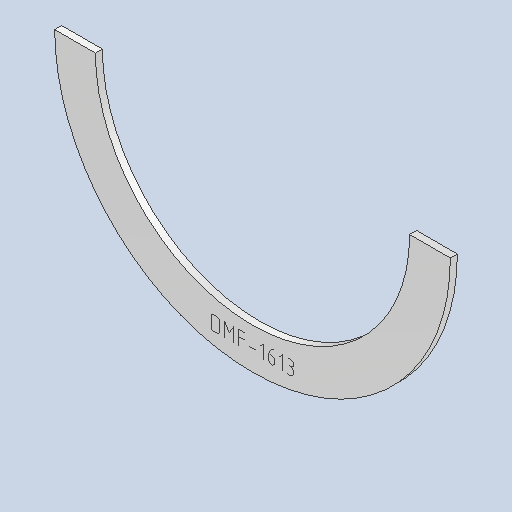
# Autodesk Inventor part: DMF-1613 Front Connector Ring 3 Half
Saved by Autodesk Inventor 2026.2 (Build 302298000, 298)
## iProperties
Created: 2024-04-30
Part Number: DMF-1613 Front Connector Ring 3 Half
Material: Stainless Steel AISI 304
Document SubType Name: Sheet Metal
Designer: admin
Stock Number: DMF-1613
Mass: 16.575 g
Surface Area: 188.37 cm^2
Volume: 16.575 cm^3
Density: 8 g/cm^3
Flat Pattern Width: 8.5 cm
Flat Pattern Length: 17 cm
Flat Pattern Area: 144.5 cm^2
Sheet Metal Rule: Default
Sheet Metal Width: 85,000 mm
Sheet Metal Length: 170,000 mm
Sheet Metal Area: 14450,000 mm^2
Appearance: Chrome - Satin
Author: pokla
Autodesk Inventor part; units mm, degrees
ref_plane "YZ Plane" through (0, 0, 0) normal (1, 0, 0) x (0, 1, 0)
ref_plane "XZ Plane" through (0, 0, 0) normal (0, 1, 0) x (-1, 0, 0)
ref_plane "XY Plane" through (0, 0, 0) normal (0, 0, 1) x (1, 0, 0)
sketch "Sketch1" plane through (0, 0, 0) normal (0, 0, 1) x (1, 0, 0)
  circle A0 centre (0, 0) radius 67.5
  circle A1 centre (0, 0) radius 85
  line L0 (0, 0) -> (0, 67.5) construction
  circle A2 centre (28.7013, 69.291) radius 3.5 construction
  line L1 (28.7013, 69.291) -> (0, 0) construction
  circle A3 centre (0, 0) radius 75 construction
  circle A4 centre (-28.7013, 69.291) radius 3.5 construction
  circle A5 centre (-69.291, 28.7013) radius 3.5 construction
  circle A6 centre (-69.291, -28.7013) radius 3.5 construction
  circle A7 centre (-28.7013, -69.291) radius 3.5 construction
  circle A8 centre (28.7013, -69.291) radius 3.5 construction
  circle A9 centre (69.291, -28.7013) radius 3.5 construction
  circle A10 centre (69.291, 28.7013) radius 3.5 construction
  line L2 (-18.0781, -71.6711) -> (54.6523, -71.6711) construction
  line L3 (54.6523, -71.6711) -> (54.6523, -78.0282) construction
  line L4 (54.6523, -78.0282) -> (-18.0781, -78.0282) construction
  line L5 (-18.0781, -78.0282) -> (-18.0781, -71.6711) construction
  line L6 (-85, 0) -> (85, 0)
  point P0 (0, -85)
  point P1 (67.5, 0)
  point P2 (-67.5, 0)
  dimension "d32" = 135
  dimension "d97" = 150
  dimension "d31" = 170
  dimension "d95" = 7
  dimension "d96" = 22.5
  dimension "d100" = 360
  constraints: 10 coincident, 9 centre point, 6 end point, 3 point on circle, 1 horizontal, 1 midpoint, 1 vertical, 1 vertical alignment, 25 other
  measures "d31" diameter of A1
  measures "d95" diameter of A2
  measures "d96" angle of L1 L0
extrude "Plate4" add sketch "Sketch1" against normal blind 3 contours L6 A1 A0 picked at (1.858, -78.9314)
mark "Mark3"
equation "\"d63\" = Thickness"
equation "\"BendRadius\" = Thickness"
equation "\"BendReliefWidth\" = Thickness"
equation "\"BendReliefDepth\" = 0.5 * Thickness"
equation "\"CornerReliefSize\" = 4 * Thickness"
equation "\"MinimumRemnant\" = 2 * Thickness"
equation "\"TransitionRadius\" = BendRadius"
equation "\"JacobiRadiusSize\" = BendRadius"
equation "\"GapSize\" = Thickness"
equation "\"Thickness\" = 3"
body "Solid3"
